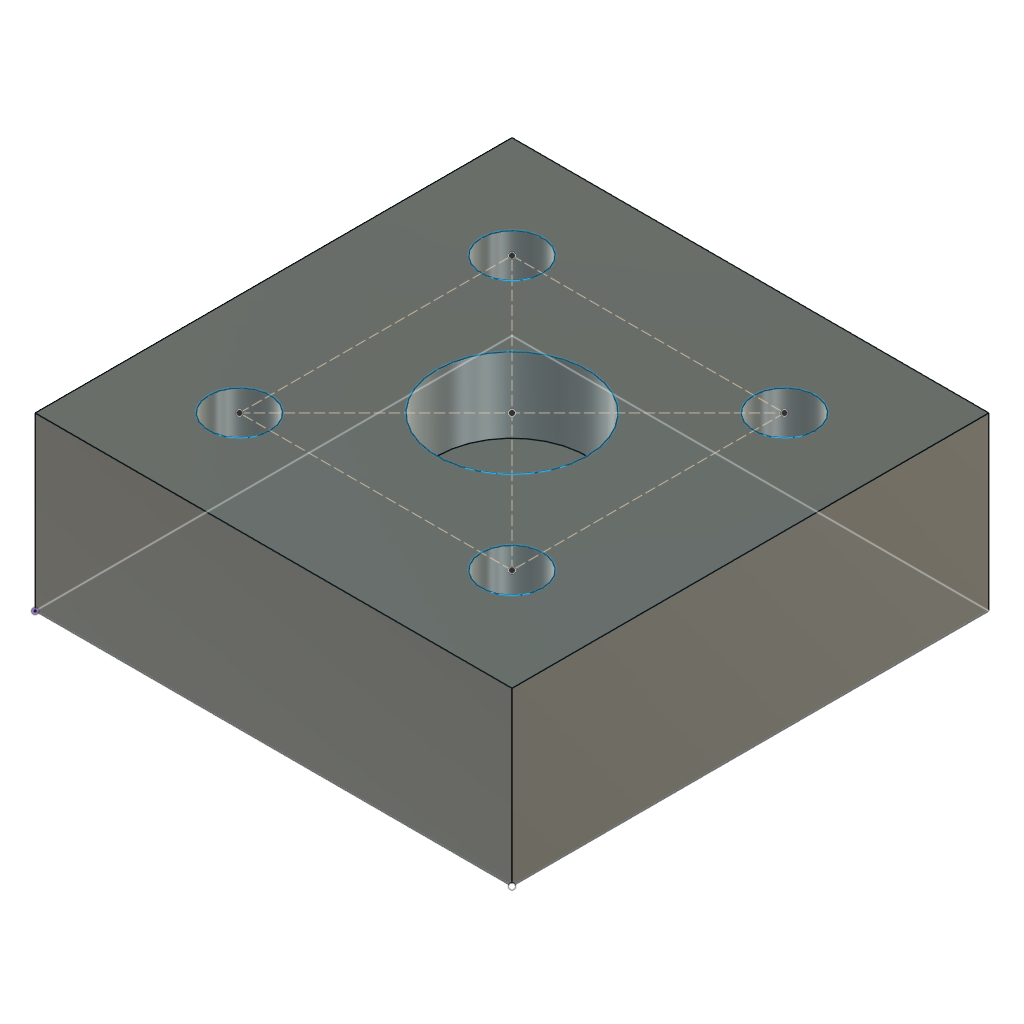
Tensile Tester (Autodesk Fusion 360 archive; units mm, degrees)
design "bearing mount"
part number: 2026-11-17-15-41-37-183
Autodesk Fusion 360 part; units mm, degrees
sketch "Sketch1" plane through (0, 0, 0) normal (0, 0, 1) x (1, 0, 0)
  line L0 (0, 0) -> (70, 0)
  line L1 (0, 0) -> (0, 70)
  line L2 (0, 70) -> (70, 70)
  line L3 (70, 70) -> (70, 0)
  dimension "d11" = 70
  dimension "d12" = 70
  dimension "d13" = 70
  dimension "d14" = 70
  constraint coincident L0.start L1.start
  constraint horizontal L0
  constraint perpendicular L0 L1
  constraint perpendicular L1 L2
  constraint perpendicular L0 L3
  measures "d11" distance of L0.start L0.end
  measures "d12" distance of L0.start L1.end
  measures "d13" distance of L1.end L2.end
  measures "d14" distance of L2.end L0.end
extrude "Extrude1" add sketch "Sketch1" along normal blind 25.18
sketch "Sketch2" plane through (0, 0, 25.18) normal (0, 0, 1) x (-1, 0, 0)
  line L0 (0, 0) -> (-70, 0)
  line L1 (-70, 0) -> (-70, -70)
  line L2 (-70, -70) -> (0, -70)
  line L3 (0, -70) -> (0, 0)
  circle A0 centre (-35, -35) radius 11.0163
  line L4 (-55, -15) -> (-15, -15) construction
  line L5 (-15, -15) -> (-15, -55) construction
  line L6 (-15, -55) -> (-55, -55) construction
  line L7 (-55, -55) -> (-55, -15) construction
  line L8 (-55, -15) -> (-15, -55) construction
  line L9 (-15, -15) -> (-55, -55) construction
  circle A1 centre (-15, -55) radius 4.5
  circle A2 centre (-55, -55) radius 4.5
  circle A3 centre (-15, -15) radius 4.5
  circle A4 centre (-55, -15) radius 4.5
  point P0 (-35, -35)
  dimension "d18" = 22.0325
  dimension "d19" = 40
  dimension "d20" = 40
  dimension "d21" = 9
  dimension "d22" = 9
  dimension "d23" = 9
  dimension "d24" = 9
  constraint horizontal L4
  constraint perpendicular L4 L5
  constraint parallel L4 L6
  constraint parallel L5 L7
  constraint coincident L8 P0
  constraint coincident L9 P0
  constraint coincident P0 A0.centre
  constraint coincident L5.end L6.start
  constraint coincident L6.end L7.start
  constraint coincident L4.end L5.start
  constraint coincident L4.start L7.end
  measures "d18" diameter of A0
  measures "d19" distance of L5.end L6.end
  measures "d20" distance of L4.end L5.end
  measures "d21" diameter of A1
  measures "d22" diameter of A2
  measures "d23" diameter of A3
  measures "d24" diameter of A4
extrude "Extrude2" cut sketch "Sketch2" against normal blind 11 contours A0
extrude "Extrude3" cut sketch "Sketch2" against normal through all contours A1 | A2 | A3 | A4
equation "mountlength = 70 mm"
equation "mountwidth = 70 mm"
equation "mountthickness = 25.18 mm"
equation "bearingdiameter = 22.0325 mm"
equation "bearingdepth = 11 mm"
equation "bottomjournal = 10 mm"
equation "mountingholes = 9 mm"
equation "coverdiameter = 42 mm"
equation "coverthickness = 2 mm"
equation "covercenteropening = 16 mm"
equation "d11 = mountlength"
equation "d12 = mountwidth"
equation "d13 = mountlength"
equation "d14 = mountwidth"
equation "d15 = mountthickness"
equation "d18 = bearingdiameter"
equation "d21 = mountingholes"
equation "d22 = mountingholes"
equation "d23 = mountingholes"
equation "d24 = mountingholes"

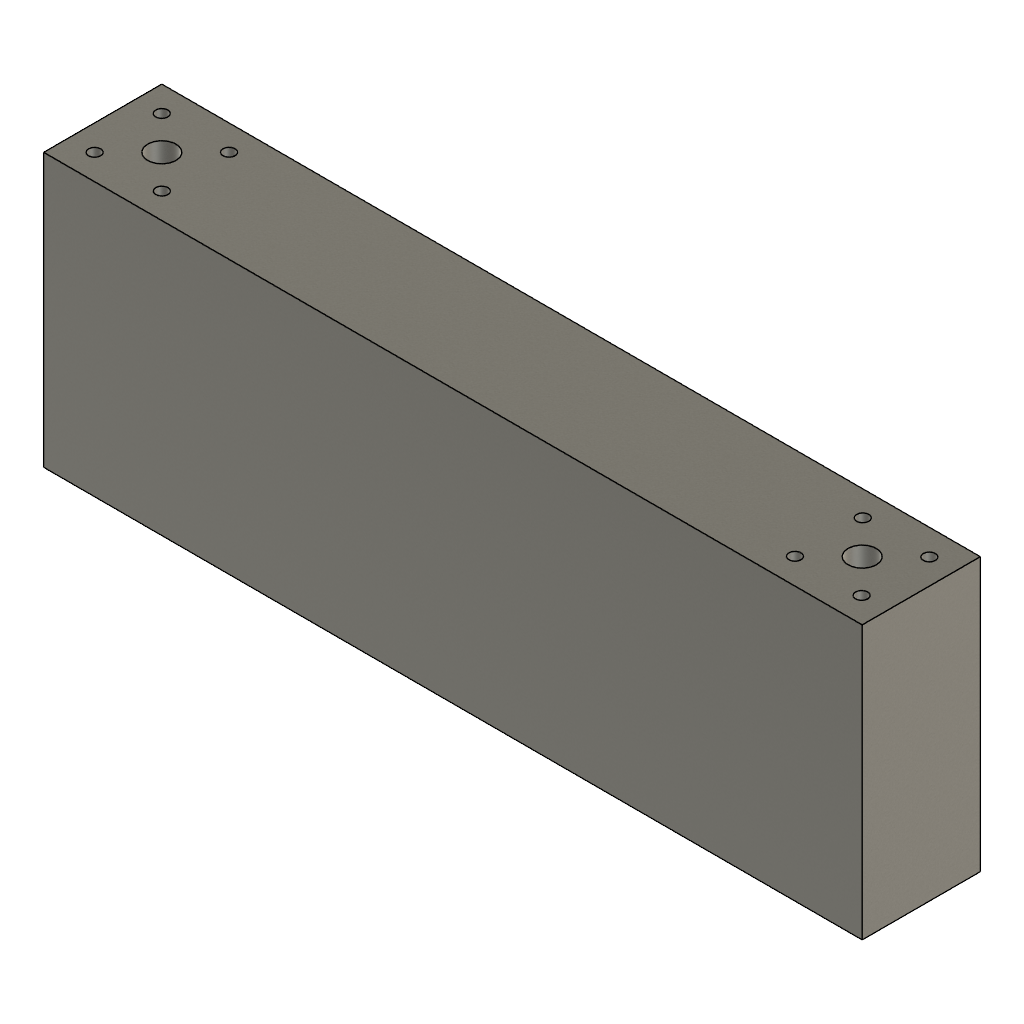
design "Crosshead"
part number: 2026-11-10-13-22-28-365
Autodesk Fusion 360 part; units mm, degrees
sketch "Sketch1" plane through (0, 0, 0) normal (0, 0, 1) x (1, 0, 0)
  line L0 (0, 0) -> (457.2, 0)
  line L1 (457.2, 0) -> (457.2, 66.04)
  line L2 (457.2, 66.04) -> (0, 66.04)
  line L3 (0, 66.04) -> (0, 0)
  dimension "d12" = 457.2
  dimension "d13" = 66.04
  dimension "d14" = 457.2
  dimension "d15" = 66.04
  constraint coincident L0.start L3.end
  constraint horizontal L0
  constraint perpendicular L0 L1
  constraint perpendicular L1 L2
  constraint perpendicular L0 L3
  measures "d12" distance of L0.start L0.end
  measures "d13" distance of L0.end L1.end
  measures "d14" distance of L1.end L2.end
  measures "d15" distance of L2.end L0.start
extrude "Extrude1" add sketch "Sketch1" along normal blind 152.4
sketch "Sketch2" plane through (0, 0, 152.4) normal (0, 0, 1) x (-1, 0, 0)
  line L0 (0, -66.04) -> (0, 0)
  line L1 (0, 0) -> (-457.2, 0)
  line L2 (-457.2, 0) -> (-457.2, -66.04)
  line L3 (-457.2, -66.04) -> (0, -66.04)
  circle A0 centre (-33.02, -33.02) radius 33.02 construction
  circle A1 centre (-424.18, -33.02) radius 33.02 construction
  circle A2 centre (-33.02, -33.02) radius 26.5906 construction
  circle A3 centre (-424.18, -33.02) radius 26.5906 construction
  line L4 (-424.4146, -59.6096) -> (-423.9454, -6.4304) construction
  line L5 (-397.5904, -33.2546) -> (-450.7696, -32.7854) construction
  line L6 (-32.9963, -59.6106) -> (-33.0437, -6.4294) construction
  line L7 (-6.4294, -32.9963) -> (-59.6106, -33.0437) construction
  circle A4 centre (-33.02, -33.02) radius 26.543 construction
  circle A5 centre (-33.02, -33.02) radius 26.543 construction
  circle A6 centre (-33.02, -33.02) radius 26.543 construction
  circle A7 centre (-424.18, -33.02) radius 26.543 construction
  circle A8 centre (-424.18, -33.02) radius 26.543 construction
  circle A9 centre (-424.18, -33.02) radius 26.543 construction
  line L8 (-33.02, -33.02) -> (-51.772, -51.8054) construction
  line L9 (-33.02, -33.02) -> (-14.2346, -51.772) construction
  line L10 (-33.02, -33.02) -> (-14.268, -14.2346) construction
  line L11 (-33.02, -33.02) -> (-51.8054, -14.268) construction
  line L12 (-424.18, -33.02) -> (-443.1136, -51.6224) construction
  line L13 (-424.18, -33.02) -> (-405.5776, -51.9536) construction
  line L14 (-424.18, -33.02) -> (-405.2464, -14.4176) construction
  line L15 (-424.18, -33.02) -> (-442.7824, -14.0864) construction
  circle A10 centre (-14.2346, -51.772) radius 3.3782
  circle A11 centre (-51.772, -51.8054) radius 3.3782
  circle A12 centre (-14.268, -14.2346) radius 3.3782
  circle A13 centre (-51.8054, -14.268) radius 3.3782
  circle A14 centre (-33.02, -33.02) radius 7.9375
  circle A15 centre (-405.5776, -51.9536) radius 3.3782
  circle A16 centre (-405.2464, -14.4176) radius 3.3782
  circle A17 centre (-442.7824, -14.0864) radius 3.3782
  circle A18 centre (-443.1136, -51.6224) radius 3.3782
  circle A19 centre (-424.18, -33.02) radius 7.9375
  point P0 (0, -33.02)
  point P1 (-457.2, -33.02)
  point P2 (-33.02, -33.02)
  point P3 (-424.18, -33.02)
  dimension "d20" = 391.16
  dimension "d21" = 66.04
  dimension "d22" = 66.04
  dimension "d23" = 53.1812
  dimension "d24" = 53.1812
  dimension "d29" = 45
  dimension "d31" = 360
  dimension "d32" = 45
  dimension "d34" = 360
  dimension "d35" = 6.7564
  dimension "d36" = 6.7564
  dimension "d37" = 6.7564
  dimension "d38" = 6.7564
  dimension "d39" = 15.875
  dimension "d40" = 6.7564
  dimension "d41" = 6.7564
  dimension "d42" = 6.7564
  dimension "d43" = 6.7564
  dimension "d44" = 15.875
  constraint midpoint L0 P0
  constraint midpoint L2 P1
  constraint coincident P2 A0.centre
  constraint coincident P3 A1.centre
  constraint concentric A0 A2
  constraint concentric A1 A3
  constraint coincident A3 L4.start
  constraint coincident A3 L4.end
  constraint perpendicular A3 L4
  constraint coincident A3 L5.start
  constraint coincident A3 L5.end
  constraint perpendicular A3 L5
  constraint coincident A2 L6.start
  constraint coincident A2 L6.end
  constraint perpendicular A2 L6
  constraint coincident A2 L7.start
  constraint coincident A2 L7.end
  constraint perpendicular A2 L7
  constraint coincident A4 L8.end
  constraint coincident A8 L12.end
  constraint coincident L9.end A10.centre
  constraint coincident L8.end A11.centre
  constraint coincident L10.end A12.centre
  constraint coincident L11.end A13.centre
  constraint coincident L13.end A15.centre
  constraint coincident L14.end A16.centre
  constraint coincident L15.end A17.centre
  constraint coincident L12.end A18.centre
  constraint concentric A7 A19
  measures "d20" distance of P2 P3
  measures "d21" diameter of A0
  measures "d22" diameter of A1
  measures "d23" diameter of A2
  measures "d24" diameter of A3
  measures "d29" angle of L7 L8
  measures "d32" angle of L5 L12
  measures "d35" diameter of A10
  measures "d36" diameter of A11
  measures "d37" diameter of A12
  measures "d38" diameter of A13
  measures "d39" diameter of A14
  measures "d40" diameter of A15
  measures "d41" diameter of A16
  measures "d42" diameter of A17
  measures "d43" diameter of A18
  measures "d44" diameter of A19
extrude "Extrude2" cut sketch "Sketch2" against normal through all contours A10 | A11 | A12 | A13 | A14 | A15 | A16 | A17 | A18 | A19
equation "CrossheadLength = 18 in"
equation "CrossheadWidth = 2.6 in"
equation "CrossheadThickness = 6 in"
equation "ScrewSpacing = 15.4 in"
equation "EndOffset = ( CrossheadLength - ScrewSpacing ) / 2"
equation "FlangeDiameter = 2.6 in"
equation "FlangeBoltCircle = 2.09375 in"
equation "FlangeHoleDiameter = 0.266 in"
equation "ScrewDiameter = 0.5 in"
equation "ScrewLength = 24 in"
equation "ScrewLead = 0.1 in"
equation "d12 = CrossheadLength"
equation "d13 = CrossheadWidth"
equation "d14 = CrossheadLength"
equation "d15 = CrossheadWidth"
equation "d16 = CrossheadThickness"
equation "d20 = ScrewSpacing"
equation "d21 = FlangeDiameter"
equation "d22 = FlangeDiameter"
equation "d23 = FlangeBoltCircle"
equation "d24 = FlangeBoltCircle"
equation "d35 = FlangeHoleDiameter"
equation "d36 = FlangeHoleDiameter"
equation "d37 = FlangeHoleDiameter"
equation "d38 = FlangeHoleDiameter"
equation "d40 = FlangeHoleDiameter"
equation "d41 = FlangeHoleDiameter"
equation "d42 = FlangeHoleDiameter"
equation "d43 = FlangeHoleDiameter"
